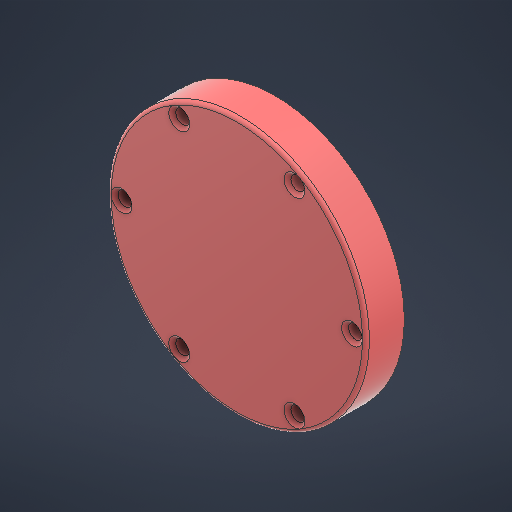
# Autodesk Inventor part: cover
Saved by Autodesk Inventor 2027.1 (Build 311270010, 270A)
## iProperties
Created: 2026-10-16
Part Number: cover
Material: Printed PLA Plastic
Document SubType Name: Modeling
Designer: youss
Density: 1.14 g/cm^3
Appearance: Default
Author: youss
Autodesk Inventor part; units mm, degrees
ref_plane "YZ Plane" through (0, 0, 0) normal (1, 0, 0) x (0, 1, 0)
ref_plane "XZ Plane" through (0, 0, 0) normal (0, 1, 0) x (-1, 0, 0)
ref_plane "XY Plane" through (0, 0, 0) normal (0, 0, 1) x (1, 0, 0)
sketch "Sketch1" plane through (0, 0, 0) normal (0, 0, 1) x (1, 0, 0)
  circle A0 centre (0, 0) radius 37
  circle A1 centre (-33, 0) radius 2
  circle A2 centre (0, 0) radius 30
  line L0 (0, 0) -> (-33, 0)
  circle A3 centre (-16.5, -28.5788) radius 2
  circle A4 centre (16.5, -28.5788) radius 2
  circle A5 centre (33, 0) radius 2
  circle A6 centre (16.5, 28.5788) radius 2
  circle A7 centre (-16.5, 28.5788) radius 2
  dimension "d13" = 60
  dimension "d14" = 74
  dimension "d15" = 4
  dimension "d16" = 33
  dimension "d19" = 360
  constraints: 8 centre point, 3 coincident, 2 end point, 1 horizontal, 13 other
  measures "d13" diameter of A2
  measures "d14" diameter of A0
  measures "d15" diameter of A1
  measures "d16" distance of point (0, 0) L0.end
extrude "Extrusion1" add sketch "Sketch1" along normal blind 4 contours A0 | A1 | A2 | A3 | A4 | A5 | A6 | A7
extrude "Extrusion2" add sketch "Sketch1" against normal blind 7 contours A0 | A3 | A4 | A5 | A6 | A7
extrude "Extrusion3" cut sketch "Sketch1" along normal through all both and the other way through all contours A1 | A3 | A4 | A5 | A6 | A7
chamfer "Chamfer1" distance 1 angle 45 6 edges at (-35, 0, 4) (-18.5, -28.5788, 4) (14.5, -28.5788, 4) (31, 0, 4) (14.5, 28.5788, 4) (-18.5, 28.5788, 4)
fillet "Fillet1" radius 1 1 edges at (-37, 0, 4)
body "Solid1"
